Autodesk Fusion 360 part; units mm, degrees
(part 2 of 2)
  point P35 (-158.2312, 30.2866)
  point P36 (-139.1812, 30.2866)
  point P37 (-120.1312, 30.2866)
  point P38 (-101.0812, 30.2866)
  point P39 (-82.0312, 30.2866)
  point P40 (-62.9812, 30.2866)
  point P41 (-43.9312, 30.2866)
  point P42 (-24.8812, 30.2866)
  point P43 (-5.8312, 30.2866)
  point P44 (13.2188, 30.2866)
  point P45 (32.2688, 30.2866)
  point P46 (51.3188, 30.2866)
  point P47 (70.3688, 30.2866)
  point P48 (89.4188, 30.2866)
  point P49 (108.4688, 30.2866)
  point P50 (141.8048, 30.2866)
  point P51 (179.9048, 30.2866)
  point P52 (198.9548, 30.2866)
  point P53 (160.8548, 30.2866)
  point P54 (-148.7069, 11.2366)
  point P55 (-129.6569, 11.2366)
  point P56 (-110.6069, 11.2366)
  point P57 (-91.5569, 11.2366)
  point P58 (-72.5069, 11.2366)
  point P59 (-53.4569, 11.2366)
  point P60 (-34.4069, 11.2366)
  point P61 (-15.3569, 11.2366)
  point P62 (3.6931, 11.2366)
  point P63 (22.7431, 11.2366)
  point P64 (41.7931, 11.2366)
  point P65 (60.8431, 11.2366)
  point P66 (79.8931, 11.2366)
  point P67 (103.7061, 11.2366)
  point P68 (160.8548, 11.2366)
  point P69 (141.8048, 11.2366)
  point P70 (160.8548, -7.8134)
  point P71 (141.8048, -7.8134)
  point P72 (179.9048, 11.2366)
  point P73 (179.9048, -7.8134)
  point P74 (179.9048, -26.8634)
  point P75 (198.9548, 11.2366)
  point P76 (-43.9312, -7.8134)
  point P77 (-62.9812, -7.8134)
  point P78 (-82.0312, -7.8134)
  point P79 (-101.0812, -7.8134)
  point P80 (70.3688, -7.8134)
  point P81 (-24.8812, -7.8134)
  point P82 (-5.8312, -7.8134)
  point P83 (32.2688, -7.8134)
  point P84 (13.2188, -7.8134)
  point P85 (-158.2312, -7.8134)
  point P86 (51.3188, -7.8134)
  point P87 (-120.1312, -7.8134)
  point P88 (-177.2812, -7.8134)
  point P89 (-139.1812, -7.8134)
  point P90 (-53.4569, -26.8634)
  point P91 (22.7431, -26.8634)
  point P92 (-72.5069, -26.8634)
  point P93 (41.7931, -26.8634)
  point P94 (-34.4069, -26.8634)
  point P95 (-91.5569, -26.8634)
  point P96 (-15.3569, -26.8634)
  point P97 (3.6931, -26.8634)
  point P98 (-129.6569, -26.8634)
  point P99 (-110.6069, -26.8634)
  point P100 (89.4188, -26.8634)
  point P101 (108.4688, -26.8634)
  point P102 (-177.2812, -26.8634)
  point P103 (-153.4692, -26.8634)
  point P104 (65.6051, -26.8634)
  point P105 (-34.4069, -45.9134)
  point P106 (98.9428, -7.8134)
  point P107 (151.3308, -26.8634)
  point P108 (198.9548, -17.3374)
  dimension "d1" = 3.5
  dimension "d3" = 4.5
  dimension "d4" = 3.5
  dimension "d6" = 4.5
  dimension "d7" = 3.5
  dimension "d8" = 106.76
  dimension "d9" = 4.5
  dimension "d10" = 3.5
  dimension "d11" = 106.76
  dimension "d12" = 4.5
  dimension "d13" = 11.5
  dimension "d14" = 2
  dimension "d15" = 2
  dimension "d17" = 2
  dimension "d18" = 11.5
  dimension "d19" = 2
  dimension "d20" = 2
  dimension "d21" = 2
  dimension "d24" = 3.5
  dimension "d25" = 3.75
  dimension "d27" = 6
  dimension "d28" = 3.5
  dimension "d30" = 3.75
  dimension "d31" = 11.5
  dimension "d32" = 6
  dimension "d33" = 4.5
  dimension "d34" = 4.5
  dimension "d35" = 4.5
  dimension "d36" = 18
  dimension "d37" = 8
  dimension "d38" = 3
  dimension "d39" = 3
  dimension "d40" = 5
  dimension "d41" = 5
  dimension "d42" = 4.5
  dimension "d43" = 8
  dimension "d44" = 9
  dimension "d45" = 4.5
  dimension "d46" = 5
  dimension "d47" = 5
  dimension "d48" = 7.5
  dimension "d49" = 4.5
  dimension "d50" = 5
  dimension "d51" = 5
  dimension "d52" = 6
  dimension "d53" = 3.5
  dimension "d54" = 17.7
  dimension "d55" = 2.5
  dimension "d56" = 7
  dimension "d57" = 3.25
  dimension "d58" = 4.5
  dimension "d59" = 7.5
  dimension "d60" = 6.5
  dimension "d62" = 6.5
  dimension "d66" = 14.15
  dimension "d67" = 14.15
  dimension "d131" = 14.15
  dimension "d132" = 14.15
  dimension "d212" = 14.15
  dimension "d213" = 14.15
  dimension "d216" = 19.05
  dimension "d219" = 19.05
  dimension "d220" = 0
  dimension "d223" = 19.05
  dimension "d224" = 0
  dimension "d225" = 14.15
  dimension "d226" = 14.15
  dimension "d229" = 114.3
  dimension "d230" = 0
  dimension "d233" = 90.486
  dimension "d234" = 0
  dimension "d237" = 19.05
  dimension "d238" = 0
  dimension "d241" = 90.486
  dimension "d242" = 0
  dimension "d245" = 23.792
  dimension "d246" = 0
  dimension "d249" = 19.05
  dimension "d250" = 0
  dimension "d253" = 23.813
  dimension "d254" = 0
  dimension "d257" = 0
  dimension "d261" = 0
  dimension "d265" = 0
  dimension "d269" = 0
  dimension "d270" = -38.1
  dimension "d273" = 0
  dimension "d274" = -38.1
  dimension "d277" = 0
  dimension "d278" = -57.15
  dimension "d281" = 0
  dimension "d290" = 23.812
  dimension "d291" = 0
  dimension "d294" = 23.812
  dimension "d295" = 0
  dimension "d298" = 0
  dimension "d303" = 28.574
  dimension "d304" = 0
  dimension "d307" = -28.574
  dimension "d308" = 0
  dimension "d311" = 0
  dimension "d312" = -28.574
  dimension "d328" = 5
  dimension "d330" = 5
  dimension "d332" = 5
  dimension "d340" = 17.25
  dimension "d341" = 17.25
  dimension "d342" = 12.25
  dimension "d343" = 12.25
  dimension "d344" = 8.0207
  dimension "d345" = 8.0207
  dimension "d346" = 65
  dimension "d348" = 16.2
  constraint vertical L133
  constraint perpendicular L126 L133
  constraint perpendicular L119 L126
  constraint vertical L156
  constraint perpendicular L150 L156
  constraint perpendicular L136 L150
  constraint perpendicular L136 L155
  constraint perpendicular L130 L155
  constraint perpendicular L130 L152
  constraint perpendicular L130 L154
  constraint perpendicular L118 L119
  constraint coincident L123.end L135
  constraint perpendicular L123 L135
  constraint coincident L121.end L122
  constraint perpendicular L121 L122
  constraint tangent A0 L123
  constraint tangent A0 L121
  constraint vertical L145
  constraint horizontal L138
  constraint vertical L147
  constraint coincident L147.end L135
  constraint coincident P0 L147
  constraint coincident P0 L138
  constraint tangent L147 A14
  constraint tangent L138 A14
  constraint tangent L138 A9
  constraint tangent A9 L145
  constraint horizontal L139
  constraint vertical L148
  constraint horizontal L143
  constraint vertical L129
  constraint horizontal L141
  constraint vertical L142
  constraint horizontal L140
  constraint vertical L144
  constraint tangent L137 A8
  constraint tangent A8 L146
  constraint tangent L131 A3
  constraint tangent A3 L132
  constraint horizontal L157
  constraint perpendicular L157 L158
  constraint parallel L157 L159
  constraint parallel L158 L160
  constraint coincident L161 P7
  constraint coincident L162 P7
  constraint horizontal L165
  constraint perpendicular L164 L165
  constraint parallel L165 L168
  constraint parallel L163 L164
  constraint coincident P2 L166
  constraint coincident P2 L167
  constraint horizontal L174
  constraint perpendicular L173 L174
  constraint parallel L171 L174
  constraint parallel L172 L173
  constraint coincident P3 L170
  constraint coincident P3 L169
  constraint horizontal L196
  constraint perpendicular L196 L198
  constraint parallel L196 L204
  constraint parallel L198 L206
  constraint coincident P7 L214
  constraint coincident P7 L216
  constraint coincident L10.end L789
  constraint perpendicular L10 L789
  constraint coincident L789 L791.end
  constraint perpendicular L789 L791
  constraint coincident L77.start L792
  constraint perpendicular L77 L792
  constraint coincident L24.end L792
  constraint perpendicular L24 L792
  constraint coincident L21.end L794
  constraint perpendicular L21 L794
  constraint coincident L27.start L794
  constraint perpendicular L27 L794
  constraint coincident L26.start L799
  constraint coincident L104.end L799
  constraint perpendicular L104 L799
  constraint coincident L103.end L800
  constraint perpendicular L103 L800
  constraint coincident L108.start L800
  constraint perpendicular L108 L800
  constraint coincident L22.end L807
  constraint perpendicular L22 L807
  constraint coincident L66.start L807
  constraint perpendicular L66 L807
  constraint coincident L14.start L804
  constraint perpendicular L14 L804
  constraint coincident L100.end L804
  constraint perpendicular L100 L804
  constraint perpendicular L811 L812
  constraint perpendicular L810 L815
  constraint perpendicular L3 L816
  constraint horizontal L818
  constraint perpendicular L30 L819
  constraint midpoint L31.end L813
  constraint perpendicular L36 L820
  constraint midpoint L31.start L820
  constraint midpoint L1.end L112
  constraint perpendicular L1 L112
  constraint midpoint L1.start L812
  measures "d1" diameter of A2
  measures "d3" distance of A2.centre L134
  measures "d4" diameter of A13
  measures "d6" distance of A13.centre L122
  measures "d7" diameter of A5
  measures "d8" distance of A5.centre A2.centre
  measures "d9" distance of A5.centre L120
  measures "d10" diameter of A10
  measures "d11" distance of A10.centre A13.centre
  measures "d12" distance of A10.centre L135
  measures "d13" distance of L118.end L125.end
  measures "d14" distance of L118.start L118.end
  measures "d15" distance of L126 L127
  measures "d17" distance of L125.end L125.start
  measures "d18" distance of L136.end L149.end
  measures "d19" distance of L149.start L149.end
  measures "d20" distance of L130.start L136.end
  measures "d21" distance of L150 L152
  measures "d24" diameter of A4
  measures "d25" distance of A4.centre L153
  measures "d27" distance of A4.centre L126
  measures "d28" diameter of A15
  measures "d30" distance of A15.centre L130
  measures "d31" distance of L136.start L150.start
  measures "d32" distance of A15.centre L150
  measures "d33" distance of A0.start A0.centre
  measures "d34" distance of A0.centre L135
  measures "d35" distance of A0.end A2.centre
  measures "d36" distance of L145.start L147.end
  measures "d37" distance of P0 L147.end
  measures "d38" radius of A14
  measures "d39" radius of A9
  measures "d40" distance of L139.end L129.end
  measures "d41" distance of L129.start L129.end
  measures "d42" distance of L135 L139
  measures "d43" distance of L141.end L141.start
  measures "d44" distance of L140.end L141.start
  measures "d45" distance of A8.centre L137.start
  measures "d46" diameter of A7
  measures "d47" distance of A7.centre L135
  measures "d48" horizontal distance of A7.centre A8.end
  measures "d49" distance of L137.start A13.centre
  measures "d50" diameter of A1
  measures "d51" distance of A1.centre L135
  measures "d52" horizontal distance of A9.end A13.centre
  measures "d53" distance of L147.start L148
  measures "d54" distance of L129 L142
  measures "d55" diameter of A11
  measures "d56" distance of A11.centre L144
  measures "d57" distance of A11.centre L134
  measures "d58" distance of L131.start A3.centre
  measures "d59" horizontal distance of A1.centre A0.start
  measures "d60" diameter of A6
  measures "d62" diameter of A12
  measures "d66" distance of L157.end L158.end
  measures "d67" distance of L158.end L159.end
  measures "d131" distance of L164.start L164.end
  measures "d132" distance of L164.end L163.start
  measures "d212" distance of L169.start L170.end
  measures "d213" distance of L170.end L169.end
  measures "d216" vertical distance of P2 P3
  measures "d225" distance of L157.end L158.end
  measures "d226" distance of L158.end L159.end
  measures "d328" diameter of A16
  measures "d330" diameter of A17
  measures "d332" diameter of A18
  measures "d340" horizontal distance of A12.centre A15.centre
  measures "d341" horizontal distance of A6.centre A4.centre
  measures "d342" horizontal distance of A6.centre A16.centre
  measures "d343" horizontal distance of A12.centre A17.centre
  measures "d344" distance of L12 A6.centre
  measures "d345" distance of L12 A12.centre
  measures "d346" distance of A3.centre A10.centre
  measures "d348" vertical distance of A3.centre A18.centre
extrude "Extrude4" add sketch "Plate" along normal blind 1.5 contours L2 L5 L11 L12 L120 A0 L121 L122 L123 L131 A3 L132 L134 L135 L137 L138 A8 A9 L140 L142 L144 L145 L146 L147 A14 | A16 | A17 | A18
extrude "Extrude5" cut sketch "Plate" along normal blind 1.5 contours A16
extrude "Extrude6" cut sketch "Plate" along normal blind 1.5 contours A17
extrude "Extrude7" cut sketch "Plate" along normal blind 1.5 contours A18
sketch "Sketch2" plane through (0, 0, 0) normal (1, 0, 0) x (0, 1, 0)
  line L0 (-87.1128, 33.1148) -> (87.1128, 33.1148)
  line L1 (87.1128, 33.1148) -> (87.1128, -33.1148)
  line L2 (87.1128, -33.1148) -> (-87.1128, -33.1148)
  line L3 (-87.1128, -33.1148) -> (-87.1128, 33.1148)
  line L4 (-87.1128, 33.1148) -> (87.1128, -33.1148) construction
  line L5 (87.1128, 33.1148) -> (-87.1128, -33.1148) construction
  constraint horizontal L0
  constraint perpendicular L0 L1
  constraint parallel L0 L2
  constraint parallel L1 L3
  constraint coincident L4 origin
  constraint coincident L5 origin
equation "keyswitch_cutout = 14.15 mm"
equation "keyswitch_pitch = 19.05 mm"
equation "d66 = keyswitch_cutout"
equation "d67 = keyswitch_cutout"
equation "function_key_bank_pitch = ( keyswitch_pitch * 3 ) + 57.15 mm"
equation "main_bank_to_keypad = 33.336 mm"
equation "d131 = keyswitch_cutout"
equation "d132 = keyswitch_cutout"
equation "d212 = keyswitch_cutout"
equation "d213 = keyswitch_cutout"
equation "d216 = keyswitch_pitch"
equation "d219 = keyswitch_pitch"
equation "d225 = keyswitch_cutout"
equation "d226 = keyswitch_cutout"
equation "d229 = function_key_bank_pitch"
equation "d233 = ( keyswitch_pitch * 3 ) + main_bank_to_keypad"
equation "d237 = keyswitch_pitch"
equation "d241 = ( keyswitch_pitch * 3 ) + main_bank_to_keypad"
equation "d249 = keyswitch_pitch"
equation "d258 = -keyswitch_pitch"
equation "d262 = -keyswitch_pitch"
equation "d266 = -keyswitch_pitch"
equation "d270 = -keyswitch_pitch * 2"
equation "d274 = -keyswitch_pitch * 2"
equation "d278 = -keyswitch_pitch * 3"
equation "d282 = -keyswitch_pitch"
equation "keyswitch_pitch_1_5u = keyswitch_pitch + 4.762 mm"
equation "d290 = keyswitch_pitch_1_5u"
equation "d294 = keyswitch_pitch_1_5u"
equation "d299 = -keyswitch_pitch"
equation "keyswitch_pitch_2u = keyswitch_pitch + ( ( 4.762 * 2 ) * 1 mm )"
equation "d303 = keyswitch_pitch_2u"
equation "d307 = -keyswitch_pitch_2u"
equation "d312 = -keyswitch_pitch_2u"
